Autodesk Fusion 360 part; units mm, degrees
(part 6 of 7)
sketch "Cut stock profile (62)" plane through (-287, 0, 0) normal (1, 0, 0) x (0, 0, -1) in component "rear left public turning fork"
  circle A0 centre (-38.1, 265) radius 5
ref_plane "WorkPlane1" through (-286, 0, 0) normal (1, 0, 0) x (0, 1, 0) in component "rear left public wheel axle"
sketch "New stock profile (103)" plane through (-286, 0, 0) normal (1, 0, 0) x (0, 0, -1) in component "rear left public wheel axle"
  circle A0 centre (-38.1, 265) radius 5
extrude "New 1''''''''''''''''''''''''''''''''''''''''''''''''''''''''''''''''''''''''''''''''''''''''''''''''''''''" add sketch "New stock profile (103)" along normal blind 42 separate body makes body 229 in component "rear left public wheel axle"
ref_plane "WorkPlane1" through (10, 0, 0) normal (1, 0, 0) x (0, 1, 0) in component "rear left public wheel"
sketch "New stock profile (104)" plane through (10, 0, 0) normal (1, 0, 0) x (0, 0, -1) in component "rear left public wheel"
  circle A0 centre (-10, 0) radius 38.1
  circle A1 centre (-10, 0) radius 5
extrude "New 1'''''''''''''''''''''''''''''''''''''''''''''''''''''''''''''''''''''''''''''''''''''''''''''''''''''''" add sketch "New stock profile (104)" against normal blind 26 separate body makes body 230 in component "rear left public wheel"
ref_plane "WorkPlane1" through (0, 0, 3.1) normal (0, 0, 1) x (1, 0, 0) in component "rear right public drive housing"
sketch "New stock profile (105)" plane through (0, 0, 3.1) normal (0, 0, 1) x (1, 0, 0) in component "rear right public drive housing"
  circle A0 centre (3, 3) radius 30
  circle A1 centre (3, 3) radius 20
extrude "New 1''''''''''''''''''''''''''''''''''''''''''''''''''''''''''''''''''''''''''''''''''''''''''''''''''''''''" add sketch "New stock profile (105)" along normal blind 48 separate body makes body 231 in component "rear right public drive housing"
ref_plane "WorkPlane2" through (0, 0, -1.9) normal (0, 0, 1) x (1, 0, 0) in component "rear right public drive housing"
sketch "Join stock profile (39)" plane through (0, 0, -1.9) normal (0, 0, 1) x (1, 0, 0) in component "rear right public drive housing"
  line L0 (15, 15) -> (29, 15)
  line L1 (29, 15) -> (29, 29)
  line L2 (29, 29) -> (15, 29)
  line L3 (15, 29) -> (15, 15)
extrude "Join 2''''''''''''''''''''''''''''''''''''''" add sketch "Join stock profile (39)" along normal blind 53 bodies 231 in component "rear right public drive housing"
ref_plane "WorkPlane3" through (0, 0, -4.4362) normal (0, 0, 1) x (1, 0, 0) in component "rear right public drive housing"
sketch "Join stock profile (1) (7)" plane through (0, 0, -4.4362) normal (0, 0, 1) x (1, 0, 0) in component "rear right public drive housing"
  line L0 (22, -33) -> (29, -33)
  line L1 (29, -33) -> (29, 28)
  line L2 (29, 28) -> (22, 28)
  line L3 (22, 28) -> (22, -33)
extrude "Join 3''''''" add sketch "Join stock profile (1) (7)" along normal blind 4.2863 bodies 231 in component "rear right public drive housing"
ref_plane "WorkPlane4" through (0, 0, -4.4362) normal (0, 0, 1) x (1, 0, 0) in component "rear right public drive housing"
sketch "Join stock profile (2) (8)" plane through (0, 0, -4.4362) normal (0, 0, 1) x (1, 0, 0) in component "rear right public drive housing"
  line L0 (25, -34) -> (90.7, -34)
  line L1 (90.7, -34) -> (90.7, -23)
  line L2 (90.7, -23) -> (25, -23)
  line L3 (25, -23) -> (25, -34)
extrude "Join 4''''''" add sketch "Join stock profile (2) (8)" along normal blind 4.2863 bodies 231 in component "rear right public drive housing"
ref_plane "WorkPlane5" through (0, 0, -4.4362) normal (0, 0, 1) x (1, 0, 0) in component "rear right public drive housing"
sketch "Join stock profile (3) (5)" plane through (0, 0, -4.4362) normal (0, 0, 1) x (1, 0, 0) in component "rear right public drive housing"
  line L0 (-33, 22) -> (28, 22)
  line L1 (28, 22) -> (28, 29)
  line L2 (28, 29) -> (-33, 29)
  line L3 (-33, 29) -> (-33, 22)
extrude "Join 5'''" add sketch "Join stock profile (3) (5)" along normal blind 4.2863 bodies 231 in component "rear right public drive housing"
ref_plane "WorkPlane6" through (0, 0, -4.4362) normal (0, 0, 1) x (1, 0, 0) in component "rear right public drive housing"
sketch "Join stock profile (4) (5)" plane through (0, 0, -4.4362) normal (0, 0, 1) x (1, 0, 0) in component "rear right public drive housing"
  line L0 (-34, 25) -> (-23, 25)
  line L1 (-23, 25) -> (-23, 90.7)
  line L2 (-23, 90.7) -> (-34, 90.7)
  line L3 (-34, 90.7) -> (-34, 25)
extrude "Join 6'''" add sketch "Join stock profile (4) (5)" along normal blind 4.2863 bodies 231 in component "rear right public drive housing"
ref_plane "WorkPlane7" through (0, 0, -4.4463) normal (0, 0, 1) x (1, 0, 0) in component "rear right public drive housing"
sketch "Cut stock profile (63)" plane through (0, 0, -4.4463) normal (0, 0, 1) x (1, 0, 0) in component "rear right public drive housing"
  circle A0 centre (60.15, -28.75) radius 2.5
extrude "Cut 7''''''''" cut sketch "Cut stock profile (63)" along normal blind 4.3063 bodies 231 in component "rear right public drive housing"
extrude "Extrude4''''''''''''''" [no effect] in component "rear right tab 1-1 socket screw"
ref_plane "WorkPlane8" through (0, 0, -4.4463) normal (0, 0, 1) x (1, 0, 0) in component "rear right public drive housing"
sketch "Cut stock profile (1) (17)" plane through (0, 0, -4.4463) normal (0, 0, 1) x (1, 0, 0) in component "rear right public drive housing"
  circle A0 centre (85.55, -28.75) radius 2.5
extrude "Cut 8'''" cut sketch "Cut stock profile (1) (17)" along normal blind 4.3063 bodies 231 in component "rear right public drive housing"
extrude "Extrude4'''''''''''''''" [no effect] in component "rear right tab 1-2 socket screw"
ref_plane "WorkPlane9" through (0, 0, -4.4463) normal (0, 0, 1) x (1, 0, 0) in component "rear right public drive housing"
sketch "Cut stock profile (2) (17)" plane through (0, 0, -4.4463) normal (0, 0, 1) x (1, 0, 0) in component "rear right public drive housing"
  circle A0 centre (-28.75, 60.15) radius 2.5
extrude "Cut 9'''" cut sketch "Cut stock profile (2) (17)" along normal blind 4.3063 bodies 231 in component "rear right public drive housing"
extrude "Extrude4''''''''''''''''" [no effect] in component "rear right tab 2-1 socket screw"
ref_plane "WorkPlane10" through (0, 0, -4.4463) normal (0, 0, 1) x (1, 0, 0) in component "rear right public drive housing"
sketch "Cut stock profile (3) (15)" plane through (0, 0, -4.4463) normal (0, 0, 1) x (1, 0, 0) in component "rear right public drive housing"
  circle A0 centre (-28.75, 85.55) radius 2.5
extrude "Cut 10'''" cut sketch "Cut stock profile (3) (15)" along normal blind 4.3063 bodies 231 in component "rear right public drive housing"
extrude "Extrude4'''''''''''''''''" [no effect] in component "rear right tab 2-2 socket screw"
ref_plane "WorkPlane11" through (0, 0, 50.65) normal (0, 0, 1) x (1, 0, 0) in component "rear right public drive housing"
sketch "Join stock profile (5) (5)" plane through (0, 0, 50.65) normal (0, 0, 1) x (1, 0, 0) in component "rear right public drive housing"
  line L0 (22, -33) -> (29, -33)
  line L1 (29, -33) -> (29, 28)
  line L2 (29, 28) -> (22, 28)
  line L3 (22, 28) -> (22, -33)
extrude "Join 11'''" add sketch "Join stock profile (5) (5)" along normal blind 3.6625 bodies 231 in component "rear right public drive housing"
ref_plane "WorkPlane12" through (0, 0, 50.65) normal (0, 0, 1) x (1, 0, 0) in component "rear right public drive housing"
sketch "Join stock profile (6) (5)" plane through (0, 0, 50.65) normal (0, 0, 1) x (1, 0, 0) in component "rear right public drive housing"
  line L0 (25, -34) -> (90.7, -34)
  line L1 (90.7, -34) -> (90.7, -23)
  line L2 (90.7, -23) -> (25, -23)
  line L3 (25, -23) -> (25, -34)
extrude "Join 12'''" add sketch "Join stock profile (6) (5)" along normal blind 3.6625 bodies 231 in component "rear right public drive housing"
ref_plane "WorkPlane13" through (0, 0, 50.65) normal (0, 0, 1) x (1, 0, 0) in component "rear right public drive housing"
sketch "Join stock profile (7) (5)" plane through (0, 0, 50.65) normal (0, 0, 1) x (1, 0, 0) in component "rear right public drive housing"
  line L0 (-33, 22) -> (28, 22)
  line L1 (28, 22) -> (28, 29)
  line L2 (28, 29) -> (-33, 29)
  line L3 (-33, 29) -> (-33, 22)
extrude "Join 13'''" add sketch "Join stock profile (7) (5)" along normal blind 3.6625 bodies 231 in component "rear right public drive housing"
ref_plane "WorkPlane14" through (0, 0, 50.65) normal (0, 0, 1) x (1, 0, 0) in component "rear right public drive housing"
sketch "Join stock profile (8) (5)" plane through (0, 0, 50.65) normal (0, 0, 1) x (1, 0, 0) in component "rear right public drive housing"
  line L0 (-34, 25) -> (-23, 25)
  line L1 (-23, 25) -> (-23, 90.7)
  line L2 (-23, 90.7) -> (-34, 90.7)
  line L3 (-34, 90.7) -> (-34, 25)
extrude "Join 14'''" add sketch "Join stock profile (8) (5)" along normal blind 3.6625 bodies 231 in component "rear right public drive housing"
ref_plane "WorkPlane15" through (0, 0, 50.64) normal (0, 0, 1) x (1, 0, 0) in component "rear right public drive housing"
sketch "Cut stock profile (4) (15)" plane through (0, 0, 50.64) normal (0, 0, 1) x (1, 0, 0) in component "rear right public drive housing"
  circle A0 centre (60.15, -28.75) radius 2.5
extrude "Cut 15'''" cut sketch "Cut stock profile (4) (15)" along normal blind 3.6825 bodies 231 in component "rear right public drive housing"
extrude "Extrude5''''''''''''''" [no effect] in component "rear right tab 1-1 socket screw"
extrude "Extrude2'''''''''''''''" [no effect] in component "rear right tab 1-1 locknut"
ref_plane "WorkPlane16" through (0, 0, 50.64) normal (0, 0, 1) x (1, 0, 0) in component "rear right public drive housing"
sketch "Cut stock profile (5) (13)" plane through (0, 0, 50.64) normal (0, 0, 1) x (1, 0, 0) in component "rear right public drive housing"
  circle A0 centre (85.55, -28.75) radius 2.5
extrude "Cut 16'''" cut sketch "Cut stock profile (5) (13)" along normal blind 3.6825 bodies 231 in component "rear right public drive housing"
extrude "Extrude5'''''''''''''''" [no effect] in component "rear right tab 1-2 socket screw"
extrude "Extrude2''''''''''''''''" [no effect] in component "rear right tab 1-2 locknut"
ref_plane "WorkPlane17" through (0, 0, 50.64) normal (0, 0, 1) x (1, 0, 0) in component "rear right public drive housing"
sketch "Cut stock profile (6) (5)" plane through (0, 0, 50.64) normal (0, 0, 1) x (1, 0, 0) in component "rear right public drive housing"
  circle A0 centre (-28.75, 60.15) radius 2.5
extrude "Cut 17'''" cut sketch "Cut stock profile (6) (5)" along normal blind 3.6825 bodies 231 in component "rear right public drive housing"
extrude "Extrude5''''''''''''''''" [no effect] in component "rear right tab 2-1 socket screw"
extrude "Extrude2'''''''''''''''''" [no effect] in component "rear right tab 2-1 locknut"
ref_plane "WorkPlane18" through (0, 0, 50.64) normal (0, 0, 1) x (1, 0, 0) in component "rear right public drive housing"
sketch "Cut stock profile (7) (5)" plane through (0, 0, 50.64) normal (0, 0, 1) x (1, 0, 0) in component "rear right public drive housing"
  circle A0 centre (-28.75, 85.55) radius 2.5
extrude "Cut 18'''" cut sketch "Cut stock profile (7) (5)" along normal blind 3.6825 bodies 231 in component "rear right public drive housing"
extrude "Extrude5'''''''''''''''''" [no effect] in component "rear right tab 2-2 socket screw"
extrude "Extrude2''''''''''''''''''" [no effect] in component "rear right tab 2-2 locknut"
ref_plane "WorkPlane1" through (0, 0, 6.1) normal (0, 0, 1) x (1, 0, 0) in component "rear right public motor reserve"
sketch "New stock profile (106)" plane through (0, 0, 6.1) normal (0, 0, 1) x (1, 0, 0) in component "rear right public motor reserve"
  circle A0 centre (19, 19) radius 19
extrude "New 1'''''''''''''''''''''''''''''''''''''''''''''''''''''''''''''''''''''''''''''''''''''''''''''''''''''''''" add sketch "New stock profile (106)" along normal blind 50.36 separate body makes body 232 in component "rear right public motor reserve"
ref_plane "WorkPlane1" through (0, 0, 68.1) normal (0, 0, 1) x (1, 0, 0) in component "rear right public turning fork"
sketch "New stock profile (107)" plane through (0, 0, 68.1) normal (0, 0, 1) x (1, 0, 0) in component "rear right public turning fork"
  circle A0 centre (-265, -265) radius 19.95
extrude "New 1''''''''''''''''''''''''''''''''''''''''''''''''''''''''''''''''''''''''''''''''''''''''''''''''''''''''''" add sketch "New stock profile (107)" along normal blind 23 separate body makes body 233 in component "rear right public turning fork"
ref_plane "WorkPlane2" through (0, 0, 68.1) normal (0, 0, 1) x (1, 0, 0) in component "rear right public turning fork"
sketch "Join stock profile (40)" plane through (0, 0, 68.1) normal (0, 0, 1) x (1, 0, 0) in component "rear right public turning fork"
  circle A0 centre (-265, -265) radius 25.5
extrude "Join 2'''''''''''''''''''''''''''''''''''''''" add sketch "Join stock profile (40)" along normal blind 5 bodies 233 in component "rear right public turning fork"
ref_plane "WorkPlane3" through (0, 0, 33.1) normal (0, 0, 1) x (1, 0, 0) in component "rear right public turning fork"
sketch "Join stock profile (1) (8)" plane through (0, 0, 33.1) normal (0, 0, 1) x (1, 0, 0) in component "rear right public turning fork"
  line L0 (-272, -286) -> (-258, -286)
  line L1 (-258, -286) -> (-258, -279)
  line L2 (-258, -279) -> (-272, -279)
  line L3 (-272, -279) -> (-272, -286)
extrude "Join 3'''''''" add sketch "Join stock profile (1) (8)" along normal blind 39 bodies 233 in component "rear right public turning fork"
ref_plane "WorkPlane4" through (0, 0, 33.1) normal (0, 0, 1) x (1, 0, 0) in component "rear right public turning fork"
sketch "Join stock profile (2) (9)" plane through (0, 0, 33.1) normal (0, 0, 1) x (1, 0, 0) in component "rear right public turning fork"
  line L0 (-272, -251) -> (-258, -251)
  line L1 (-258, -251) -> (-258, -244)
  line L2 (-258, -244) -> (-272, -244)
  line L3 (-272, -244) -> (-272, -251)
extrude "Join 4'''''''" add sketch "Join stock profile (2) (9)" along normal blind 39 bodies 233 in component "rear right public turning fork"
ref_plane "WorkPlane5" through (0, -287, 0) normal (0, 1, 0) x (0, 0, 1) in component "rear right public turning fork"
sketch "Cut stock profile (64)" plane through (0, -287, 0) normal (0, 1, 0) x (1, 0, 0) in component "rear right public turning fork"
  circle A0 centre (-265, -38.1) radius 5
ref_plane "WorkPlane1" through (0, -286, 0) normal (0, 1, 0) x (0, 0, 1) in component "rear right public wheel axle"
sketch "New stock profile (108)" plane through (0, -286, 0) normal (0, 1, 0) x (1, 0, 0) in component "rear right public wheel axle"
  circle A0 centre (-265, -38.1) radius 5
extrude "New 1'''''''''''''''''''''''''''''''''''''''''''''''''''''''''''''''''''''''''''''''''''''''''''''''''''''''''''" add sketch "New stock profile (108)" along normal blind 42 separate body makes body 234 in component "rear right public wheel axle"
ref_plane "WorkPlane1" through (0, 0, 3) normal (0, 0, 1) x (1, 0, 0) in component "rear right public wheel"
sketch "New stock profile (109)" plane through (0, 0, 3) normal (0, 0, 1) x (1, 0, 0) in component "rear right public wheel"
  circle A0 centre (-3, 0) radius 38.1
  circle A1 centre (-3, 0) radius 5
extrude "New 1''''''''''''''''''''''''''''''''''''''''''''''''''''''''''''''''''''''''''''''''''''''''''''''''''''''''''''" add sketch "New stock profile (109)" along normal blind 26 separate body makes body 235 in component "rear right public wheel"
ref_plane "WorkPlane1" through (0, 0, 38.1) normal (0, 0, 1) x (1, 0, 0)
sketch "Module joint datum" plane through (0, 0, 38.1) normal (0, 0, 1) x (1, 0, 0)
  point P0 (265, 265)
ref_plane "WorkPlane2" through (0, 0, 38.1) normal (0, 0, 1) x (1, 0, 0)
sketch "Module joint datum (1)" plane through (0, 0, 38.1) normal (0, 0, 1) x (1, 0, 0)
  point P0 (265, -265)
ref_plane "WorkPlane3" through (0, 0, 38.1) normal (0, 0, 1) x (1, 0, 0)
sketch "Module joint datum (2)" plane through (0, 0, 38.1) normal (0, 0, 1) x (1, 0, 0)
  point P0 (-265, 265)
ref_plane "WorkPlane4" through (0, 0, 38.1) normal (0, 0, 1) x (1, 0, 0)
sketch "Module joint datum (3)" plane through (0, 0, 38.1) normal (0, 0, 1) x (1, 0, 0)
  point P0 (-265, -265)
ref_plane "WorkPlane7" through (0, -22.225, 0) normal (0, 1, 0) x (0, 0, 1) in component "rear perimeter tube"
sketch "Cut stock profile (5) (14)" plane through (0, -22.225, 0) normal (0, 1, 0) x (1, 0, 0) in component "rear perimeter tube"
  line L0 (9.525, 1) -> (-9.525, 1)
  line L1 (-9.525, 1) -> (-9.525, -630.2)
  line L2 (-9.525, -630.2) -> (9.525, -630.2)
  line L3 (9.525, -630.2) -> (9.525, 1)
extrude "Cut 1" cut sketch "Cut stock profile (5) (14)" along normal blind 44.45 bodies 127 in component "rear perimeter tube"
ref_plane "WorkPlane8" through (-9.2, 0, 0) normal (1, 0, 0) x (0, 1, 0) in component "rear perimeter tube"
sketch "Cut stock profile (6) (6)" plane through (-9.2, 0, 0) normal (1, 0, 0) x (0, 0, -1) in component "rear perimeter tube"
  circle A0 centre (-509.75, -5.3) radius 6.55
extrude "Cut 1 (1)" cut sketch "Cut stock profile (6) (6)" against normal blind 4.5 bodies 127 in component "rear perimeter tube"
ref_plane "WorkPlane9" through (-9.2, 0, 0) normal (1, 0, 0) x (0, 1, 0) in component "rear perimeter tube"
sketch "Cut stock profile (7) (6)" plane through (-9.2, 0, 0) normal (1, 0, 0) x (0, 0, -1) in component "rear perimeter tube"
  circle A0 centre (-509.75, 15.7) radius 6.55
extrude "Cut 1 (2)" cut sketch "Cut stock profile (7) (6)" against normal blind 4.5 bodies 127 in component "rear perimeter tube"
ref_plane "WorkPlane10" through (-9.2, 0, 0) normal (1, 0, 0) x (0, 1, 0) in component "rear perimeter tube"
sketch "Cut stock profile (8) (2)" plane through (-9.2, 0, 0) normal (1, 0, 0) x (0, 0, -1) in component "rear perimeter tube"
  circle A0 centre (-119.45, -5.3) radius 6.55
extrude "Cut 1 (3)" cut sketch "Cut stock profile (8) (2)" against normal blind 4.5 bodies 127 in component "rear perimeter tube"
ref_plane "WorkPlane11" through (-9.2, 0, 0) normal (1, 0, 0) x (0, 1, 0) in component "rear perimeter tube"
sketch "Cut stock profile (9) (2)" plane through (-9.2, 0, 0) normal (1, 0, 0) x (0, 0, -1) in component "rear perimeter tube"
  circle A0 centre (-119.45, 15.7) radius 6.55
extrude "Cut 1 (4)" cut sketch "Cut stock profile (9) (2)" against normal blind 4.5 bodies 127 in component "rear perimeter tube"
ref_plane "WorkPlane7" through (9.2, 0, 0) normal (1, 0, 0) x (0, 1, 0) in component "right perimeter tube"
sketch "Cut stock profile (5) (15)" plane through (9.2, 0, 0) normal (1, 0, 0) x (0, 0, -1) in component "right perimeter tube"
  circle A0 centre (-535.15, -5.3) radius 6.55
extrude "Cut 1'" cut sketch "Cut stock profile (5) (15)" along normal blind 4.5 bodies 128 in component "right perimeter tube"
ref_plane "WorkPlane8" through (9.2, 0, 0) normal (1, 0, 0) x (0, 1, 0) in component "right perimeter tube"
sketch "Cut stock profile (6) (7)" plane through (9.2, 0, 0) normal (1, 0, 0) x (0, 0, -1) in component "right perimeter tube"
  circle A0 centre (-535.15, 15.7) radius 6.55
extrude "Cut 1 (1)'" cut sketch "Cut stock profile (6) (7)" along normal blind 4.5 bodies 128 in component "right perimeter tube"
ref_plane "WorkPlane9" through (9.2, 0, 0) normal (1, 0, 0) x (0, 1, 0) in component "right perimeter tube"
sketch "Cut stock profile (7) (7)" plane through (9.2, 0, 0) normal (1, 0, 0) x (0, 0, -1) in component "right perimeter tube"
  circle A0 centre (-144.85, -5.3) radius 6.55
extrude "Cut 1 (2)'" cut sketch "Cut stock profile (7) (7)" along normal blind 4.5 bodies 128 in component "right perimeter tube"
ref_plane "WorkPlane10" through (9.2, 0, 0) normal (1, 0, 0) x (0, 1, 0) in component "right perimeter tube"
sketch "Cut stock profile (8) (3)" plane through (9.2, 0, 0) normal (1, 0, 0) x (0, 0, -1) in component "right perimeter tube"
  circle A0 centre (-144.85, 15.7) radius 6.55
extrude "Cut 1 (3)'" cut sketch "Cut stock profile (8) (3)" along normal blind 4.5 bodies 128 in component "right perimeter tube"
ref_plane "WorkPlane5" through (9.2, 0, 0) normal (1, 0, 0) x (0, 1, 0) in component "right front return"
sketch "Cut stock profile (3) (16)" plane through (9.2, 0, 0) normal (1, 0, 0) x (0, 0, -1) in component "right front return"
  circle A0 centre (-119.45, -5.3) radius 6.55
extrude "Cut 1''" cut sketch "Cut stock profile (3) (16)" along normal blind 4.5 bodies 129 in component "right front return"
ref_plane "WorkPlane6" through (9.2, 0, 0) normal (1, 0, 0) x (0, 1, 0) in component "right front return"
sketch "Cut stock profile (4) (16)" plane through (9.2, 0, 0) normal (1, 0, 0) x (0, 0, -1) in component "right front return"
  circle A0 centre (-119.45, 15.7) radius 6.55
extrude "Cut 1 (1)''" cut sketch "Cut stock profile (4) (16)" along normal blind 4.5 bodies 129 in component "right front return"
ref_plane "WorkPlane3" through (0, -14.4752, 0) normal (0, 1, 0) x (0, 0, 1) in component "right floor sill"
sketch "Cut stock profile (1) (18)" plane through (0, -14.4752, 0) normal (0, 1, 0) x (1, 0, 0) in component "right floor sill"
  line L0 (4.0498, 1) -> (4.0498, -481)
  line L1 (4.0498, -481) -> (19.9502, -481)
  line L2 (19.9502, -481) -> (19.9502, 1)
  line L3 (19.9502, 1) -> (4.0498, 1)
extrude "Cut 1'''" cut sketch "Cut stock profile (1) (18)" along normal blind 15.9004 bodies 130 in component "right floor sill"
ref_plane "WorkPlane7" through (-9.2, 0, 0) normal (1, 0, 0) x (0, 1, 0) in component "left perimeter tube"
sketch "Cut stock profile (5) (16)" plane through (-9.2, 0, 0) normal (1, 0, 0) x (0, 0, -1) in component "left perimeter tube"
  circle A0 centre (-535.15, -5.3) radius 6.55
extrude "Cut 1''''" cut sketch "Cut stock profile (5) (16)" against normal blind 4.5 bodies 133 in component "left perimeter tube"
ref_plane "WorkPlane8" through (-9.2, 0, 0) normal (1, 0, 0) x (0, 1, 0) in component "left perimeter tube"
sketch "Cut stock profile (6) (8)" plane through (-9.2, 0, 0) normal (1, 0, 0) x (0, 0, -1) in component "left perimeter tube"
  circle A0 centre (-535.15, 15.7) radius 6.55
extrude "Cut 1 (1)'''" cut sketch "Cut stock profile (6) (8)" against normal blind 4.5 bodies 133 in component "left perimeter tube"
ref_plane "WorkPlane9" through (-9.2, 0, 0) normal (1, 0, 0) x (0, 1, 0) in component "left perimeter tube"
sketch "Cut stock profile (7) (8)" plane through (-9.2, 0, 0) normal (1, 0, 0) x (0, 0, -1) in component "left perimeter tube"
  circle A0 centre (-144.85, -5.3) radius 6.55
extrude "Cut 1 (2)''" cut sketch "Cut stock profile (7) (8)" against normal blind 4.5 bodies 133 in component "left perimeter tube"
ref_plane "WorkPlane10" through (-9.2, 0, 0) normal (1, 0, 0) x (0, 1, 0) in component "left perimeter tube"
sketch "Cut stock profile (8) (4)" plane through (-9.2, 0, 0) normal (1, 0, 0) x (0, 0, -1) in component "left perimeter tube"
  circle A0 centre (-144.85, 15.7) radius 6.55
extrude "Cut 1 (3)''" cut sketch "Cut stock profile (8) (4)" against normal blind 4.5 bodies 133 in component "left perimeter tube"
ref_plane "WorkPlane5" through (9.2, 0, 0) normal (1, 0, 0) x (0, 1, 0) in component "left front return"
sketch "Cut stock profile (3) (17)" plane through (9.2, 0, 0) normal (1, 0, 0) x (0, 0, -1) in component "left front return"
  circle A0 centre (-45.15, -5.3) radius 6.55
extrude "Cut 1'''''" cut sketch "Cut stock profile (3) (17)" along normal blind 4.5 bodies 134 in component "left front return"
ref_plane "WorkPlane6" through (9.2, 0, 0) normal (1, 0, 0) x (0, 1, 0) in component "left front return"
sketch "Cut stock profile (4) (17)" plane through (9.2, 0, 0) normal (1, 0, 0) x (0, 0, -1) in component "left front return"
  circle A0 centre (-45.15, 15.7) radius 6.55
extrude "Cut 1 (1)''''" cut sketch "Cut stock profile (4) (17)" along normal blind 4.5 bodies 134 in component "left front return"
ref_plane "WorkPlane3" through (0, -14.4752, 0) normal (0, 1, 0) x (0, 0, 1) in component "left floor sill"
sketch "Cut stock profile (1) (19)" plane through (0, -14.4752, 0) normal (0, 1, 0) x (1, 0, 0) in component "left floor sill"
  line L0 (-19.9502, 1) -> (-19.9502, -481)
  line L1 (-19.9502, -481) -> (-4.0498, -481)
  line L2 (-4.0498, -481) -> (-4.0498, 1)
  line L3 (-4.0498, 1) -> (-19.9502, 1)
extrude "Cut 1''''''" cut sketch "Cut stock profile (1) (19)" along normal blind 15.9004 bodies 135 in component "left floor sill"
ref_plane "WorkPlane6" through (0, 287, 0) normal (0, 1, 0) x (0, 0, 1) in component "front left public turning fork"
sketch "Cut stock profile (1) (20)" plane through (0, 287, 0) normal (0, 1, 0) x (1, 0, 0) in component "front left public turning fork"
  circle A0 centre (265, -38.1) radius 5
extrude "Cut 1'''''''" cut sketch "Cut stock profile (1) (20)" against normal blind 44 bodies 218 in component "front left public turning fork"
ref_plane "WorkPlane6" through (287, 0, 0) normal (1, 0, 0) x (0, 1, 0) in component "front right public turning fork"
sketch "Cut stock profile (1) (21)" plane through (287, 0, 0) normal (1, 0, 0) x (0, 0, -1) in component "front right public turning fork"
  circle A0 centre (-38.1, -265) radius 5
extrude "Cut 1''''''''" cut sketch "Cut stock profile (1) (21)" against normal blind 44 bodies 223 in component "front right public turning fork"
ref_plane "WorkPlane6" through (-287, 0, 0) normal (1, 0, 0) x (0, 1, 0) in component "rear left public turning fork"
sketch "Cut stock profile (1) (22)" plane through (-287, 0, 0) normal (1, 0, 0) x (0, 0, -1) in component "rear left public turning fork"
  circle A0 centre (-38.1, 265) radius 5
extrude "Cut 1'''''''''" cut sketch "Cut stock profile (1) (22)" along normal blind 44 bodies 228 in component "rear left public turning fork"
ref_plane "WorkPlane6" through (0, -287, 0) normal (0, 1, 0) x (0, 0, 1) in component "rear right public turning fork"
sketch "Cut stock profile (1) (23)" plane through (0, -287, 0) normal (0, 1, 0) x (1, 0, 0) in component "rear right public turning fork"
  circle A0 centre (-265, -38.1) radius 5
extrude "Cut 1''''''''''" cut sketch "Cut stock profile (1) (23)" along normal blind 44 bodies 233 in component "rear right public turning fork"
component "left perimeter tube" placed x (0, 1, 0) y (0, 0, 1) z (1, 0, 0) at (-340, 327.3, 89.4)
component "left front return" placed x (-1, 0, 0) y (0, 0, 1) z (0, 1, 0) at (327.3, 150, 89.4)
component "left blue side bumper" placed x (1, 0, 0) y (0, 1, 0) z (0, 0, 1) at (0, 378, 48)
component "left blue front bumper" placed x (1, 0, 0) y (0, 1, 0) z (0, 0, 1) at (378, 245, 48)
component "right perimeter tube" placed x (0, 1, 0) y (0, 0, 1) z (1, 0, 0) at (-340, -327.3, 89.4)
component "right front return" placed x (-1, 0, 0) y (0, 0, 1) z (0, 1, 0) at (327.3, -314.6, 89.4)
component "right blue side bumper" placed x (1, 0, 0) y (0, 1, 0) z (0, 0, 1) at (0, -378, 48)
component "right blue front bumper" placed x (1, 0, 0) y (0, 1, 0) z (0, 0, 1) at (378, -245, 48)
component "rear perimeter tube" placed x (-1, 0, 0) y (0, 0, 1) z (0, 1, 0) at (-327.3, -314.6, 89.4)
component "rear blue bumper" placed x (1, 0, 0) y (0, 1, 0) z (0, 0, 1) at (-378, 0, 48)
component "front left module tab spacer 1" placed x (1, 0, 0) y (0, 1, 0) z (0, 0, 1) at (198, 303.05, 78.32)
component "front left module tab spacer 2" placed x (1, 0, 0) y (0, 1, 0) z (0, 0, 1) at (303.05, 198, 78.32)
component "front right module tab spacer 1" placed x (1, 0, 0) y (0, 1, 0) z (0, 0, 1) at (303.05, -198, 78.32)
component "front right module tab spacer 2" placed x (1, 0, 0) y (0, 1, 0) z (0, 0, 1) at (198, -303.05, 78.32)
component "rear left module tab spacer 1" placed x (1, 0, 0) y (0, 1, 0) z (0, 0, 1) at (-303.05, 198, 78.32)
component "rear left module tab spacer 2" placed x (1, 0, 0) y (0, 1, 0) z (0, 0, 1) at (-198, 303.05, 78.32)
component "rear right module tab spacer 1" placed x (1, 0, 0) y (0, 1, 0) z (0, 0, 1) at (-198, -303.05, 78.32)
component "rear right module tab spacer 2" placed x (1, 0, 0) y (0, 1, 0) z (0, 0, 1) at (-303.05, -198, 78.32)
component "rear right hopper post" placed x (1, 0, 0) y (0, 1, 0) z (0, 0, 1) at (-188, -306, 115)
component "front right hopper post" placed x (1, 0, 0) y (0, 1, 0) z (0, 0, 1) at (176, -306, 115)
component "right floor sill" placed x (0, 1, 0) y (0, 0, 1) z (1, 0, 0) at (-330, -306, 227)
component "rear left hopper post" placed x (1, 0, 0) y (0, 1, 0) z (0, 0, 1) at (-188, 306, 115)
component "front left hopper post" placed x (1, 0, 0) y (0, 1, 0) z (0, 0, 1) at (176, 306, 115)
component "left floor sill" placed x (0, 1, 0) y (0, 0, 1) z (1, 0, 0) at (-330, 306, 227)
component "rear deck crossmember" placed x (-1, 0, 0) y (0, 0, 1) z (0, 1, 0) at (-188, -315, 113)
component "front deck crossmember" placed x (-1, 0, 0) y (0, 0, 1) z (0, 1, 0) at (176, -315, 113)
component "left electronics deck" placed x (1, 0, 0) y (0, 1, 0) z (0, 0, 1) at (-5.5, 149, 122)
component "right electronics deck" placed x (1, 0, 0) y (0, 1, 0) z (0, 0, 1) at (-5.5, -147.5, 122)
component "fore electronics deck bridge" placed x (1, 0, 0) y (0, 1, 0) z (0, 0, 1) at (110.5, 1.5, 122)
component "aft electronics deck bridge" placed x (1, 0, 0) y (0, 1, 0) z (0, 0, 1) at (-157.5, 1.5, 122)
component "battery cradle floor" placed x (1, 0, 0) y (0, 1, 0) z (0, 0, 1) at (-41.5, 1.5, 44)
component "battery cradle wall -44" placed x (1, 0, 0) y (0, 1, 0) z (0, 0, 1) at (-41.5, -42, 48)
component "battery cradle wall 43" placed x (1, 0, 0) y (0, 1, 0) z (0, 0, 1) at (-41.5, 45, 48)
component "battery secured envelope" placed x (1, 0, 0) y (0, 1, 0) z (0, 0, 1) at (-41.5, 2, 48)
component "distribution enclosure reserve" placed x (1, 0, 0) y (0, 1, 0) z (0, 0, 1) at (105, -3, 129)
component "robot controller reserve" placed x (1, 0, 0) y (0, 1, 0) z (0, 0, 1) at (-79.5, 108, 129)
component "field radio reserve" placed x (1, 0, 0) y (0, 1, 0) z (0, 0, 1) at (-88.5, -118.5, 129)
component "drive controller reserve 1" placed x (1, 0, 0) y (0, 1, 0) z (0, 0, 1) at (-120.5, -204, 129)
component "drive controller reserve 2" placed x (1, 0, 0) y (0, 1, 0) z (0, 0, 1) at (-120.5, 204, 129)
component "drive controller reserve 3" placed x (1, 0, 0) y (0, 1, 0) z (0, 0, 1) at (-42.5, -204, 129)
component "drive controller reserve 4" placed x (1, 0, 0) y (0, 1, 0) z (0, 0, 1) at (-42.5, 204, 129)
component "drive controller reserve 5" placed x (1, 0, 0) y (0, 1, 0) z (0, 0, 1) at (35.5, -204, 129)
component "drive controller reserve 6" placed x (1, 0, 0) y (0, 1, 0) z (0, 0, 1) at (35.5, 204, 129)
component "drive controller reserve 7" placed x (1, 0, 0) y (0, 1, 0) z (0, 0, 1) at (113.5, -204, 129)
component "drive controller reserve 8" placed x (1, 0, 0) y (0, 1, 0) z (0, 0, 1) at (113.5, 204, 129)
component "hopper back panel" placed x (1, 0, 0) y (0, 1, 0) z (0, 0, 1) at (-332, 0, 232)
component "right hopper wall" placed x (1, 0, 0) y (0, 1, 0) z (0, 0, 1) at (-91, -313, 232)
component "right hopper front wing" placed x (1, 0, 0) y (0, 1, 0) z (0, 0, 1) at (150, -199, 232)
component "right cross feed deck" placed x (1, 0, 0) y (0, 1, 0) z (0, 0, 1) at (-91, -199, 230)
component "right front elevator upright" placed x (1, 0, 0) y (0, 1, 0) z (0, 0, 1) at (183, -105, 111)
component "right rear elevator upright" placed x (1, 0, 0) y (0, 1, 0) z (0, 0, 1) at (319, -105, 113)
component "right elevator upper tie" placed x (0, 1, 0) y (0, 0, 1) z (1, 0, 0) at (181, -105, 637)
component "right inside lift belt" placed x (1, 0, 0) y (0, 1, 0) z (0, 0, 1) at (196, -91, 86)
component "right outside lift belt" placed x (1, 0, 0) y (0, 1, 0) z (0, 0, 1) at (301, -91, 86)
component "right lift shelf 1" placed x (1, 0, 0) y (0, 1, 0) z (0, 0, 1) at (244, -81, 99)
component "right lift shelf 2" placed x (1, 0, 0) y (0, 1, 0) z (0, 0, 1) at (244, -81, 258)
component "right lift shelf 3" placed x (1, 0, 0) y (0, 1, 0) z (0, 0, 1) at (244, -81, 417)
component "right lift shelf 4" placed x (1, 0, 0) y (0, 1, 0) z (0, 0, 1) at (244, -81, 576)
component "right intake ramp" placed x (0, 1, 0) y (0.257178, 0, 0.966364) z (0.966364, 0, -0.257178) at (213, -60, 48)
component "left hopper wall" placed x (1, 0, 0) y (0, 1, 0) z (0, 0, 1) at (-91, 313, 232)
component "left hopper front wing" placed x (1, 0, 0) y (0, 1, 0) z (0, 0, 1) at (150, 199, 232)
component "left cross feed deck" placed x (1, 0, 0) y (0, 1, 0) z (0, 0, 1) at (-91, 199, 230)
component "left front elevator upright" placed x (1, 0, 0) y (0, 1, 0) z (0, 0, 1) at (183, 105, 111)
component "left rear elevator upright" placed x (1, 0, 0) y (0, 1, 0) z (0, 0, 1) at (319, 105, 113)
component "left elevator upper tie" placed x (0, 1, 0) y (0, 0, 1) z (1, 0, 0) at (181, 105, 637)
component "left inside lift belt" placed x (1, 0, 0) y (0, 1, 0) z (0, 0, 1) at (196, 91, 86)
component "left outside lift belt" placed x (1, 0, 0) y (0, 1, 0) z (0, 0, 1) at (301, 91, 86)
component "left lift shelf 1" placed x (1, 0, 0) y (0, 1, 0) z (0, 0, 1) at (244, 81, 99)
component "left lift shelf 2" placed x (1, 0, 0) y (0, 1, 0) z (0, 0, 1) at (244, 81, 258)
component "left lift shelf 3" placed x (1, 0, 0) y (0, 1, 0) z (0, 0, 1) at (244, 81, 417)
component "left lift shelf 4" placed x (1, 0, 0) y (0, 1, 0) z (0, 0, 1) at (244, 81, 576)
component "left intake ramp" placed x (0, 1, 0) y (0.257178, 0, 0.966364) z (0.966364, 0, -0.257178) at (213, 60, 48)
component "central fore-aft feed deck" placed x (1, 0, 0) y (0, 1, 0) z (0, 0, 1) at (-90.5, 0, 230)
component "left lower lift stub shaft" placed x (-1, 0, 0) y (0, 0, 1) z (0, 1, 0) at (248, 88, 84)
component "right lower lift stub shaft" placed x (-1, 0, 0) y (0, 0, 1) z (0, 1, 0) at (248, -116, 84)
component "left upper lift stub shaft" placed x (-1, 0, 0) y (0, 0, 1) z (0, 1, 0) at (248, 88, 622)
component "right upper lift stub shaft" placed x (-1, 0, 0) y (0, 0, 1) z (0, 1, 0) at (248, -116, 622)
component "ground intake roller" placed x (-1, 0, 0) y (0, 0, 1) z (0, 1, 0) at (285.7664, -126, 342.4358)
component "right intake bearing arm" placed x (0.994522, 0, -0.104528) y (0, 1, 0) z (0.104528, 0, 0.994522) at (275, -150, 240)
component "right intake pivot plate" placed x (0, -1, 0) y (-0.17238, 0, 0.98503) z (-0.98503, 0, -0.17238) at (315, -150, 247)
component "right intake pivot axle" placed x (-1, 0, 0) y (0, 0, 1) z (0, 1, 0) at (275, -150, 240)
component "right intake journal" placed x (-1, 0, 0) y (0, 0, 1) z (0, 1, 0) at (285.7664, -150, 342.4358)
component "right upper head cheek" placed x (1, 0, 0) y (0, 1, 0) z (0, 0, 1) at (236, -150, 562)
component "left intake bearing arm" placed x (0.994522, 0, -0.104528) y (0, 1, 0) z (0.104528, 0, 0.994522) at (275, 150, 240)
component "left intake pivot plate" placed x (0, -1, 0) y (-0.17238, 0, 0.98503) z (-0.98503, 0, -0.17238) at (315, 150, 247)
component "left intake pivot axle" placed x (-1, 0, 0) y (0, 0, 1) z (0, 1, 0) at (275, 100, 240)
component "left intake journal" placed x (-1, 0, 0) y (0, 0, 1) z (0, 1, 0) at (285.7664, 126, 342.4358)
component "left upper head cheek" placed x (1, 0, 0) y (0, 1, 0) z (0, 0, 1) at (236, 150, 562)
component "right scoring wheel" placed x (0, -1, 0) y (0.5, 0, 0.866025) z (-0.866025, 0, 0.5) at (259.6506, -104, 588.5)
component "right scoring spindle" placed x (0, -1, 0) y (0.5, 0, 0.866025) z (-0.866025, 0, 0.5) at (269.1769, -104, 583)
component "right upper guide" placed x (0, 1, 0) y (-0.841019, 0, 0.541006) z (0.541006, 0, 0.841019) at (190, -80, 548)
component "right scoring bearing bridge -33" placed x (-1, 0, 0) y (0, 0, 1) z (0, 1, 0) at (266.5788, -146, 584.5)
component "right scoring bearing bridge 33" placed x (-1, 0, 0) y (0, 0, 1) z (0, 1, 0) at (209.4212, -146, 617.5)
component "left scoring wheel" placed x (0, -1, 0) y (0.5, 0, 0.866025) z (-0.866025, 0, 0.5) at (259.6506, 104, 588.5)
component "left scoring spindle" placed x (0, -1, 0) y (0.5, 0, 0.866025) z (-0.866025, 0, 0.5) at (269.1769, 104, 583)
component "left upper guide" placed x (0, 1, 0) y (-0.841019, 0, 0.541006) z (0.541006, 0, 0.841019) at (190, 80, 548)
component "left scoring bearing bridge -33" placed x (-1, 0, 0) y (0, 0, 1) z (0, 1, 0) at (266.5788, 104, 584.5)
component "left scoring bearing bridge 33" placed x (-1, 0, 0) y (0, 0, 1) z (0, 1, 0) at (209.4212, 104, 617.5)
component "left feed diverter pivot" placed x (-1, 0, 0) y (0, 0, 1) z (0, 1, 0) at (156, 76, 548)
component "right feed diverter pivot" placed x (-1, 0, 0) y (0, 0, 1) z (0, 1, 0) at (156, -100, 548)
component "feed diverter vane" placed x (1, 0, 0) y (0, 1, 0) z (0, 0, 1) at (156, 0, 548)
component "front left public wheel" placed x (-1, 0, 0) y (0, 0, 1) z (0, 1, 0) at (268, 255, 38.1)
component "front left public drive housing" placed x (1, 0, 0) y (0, 1, 0) z (0, 0, 1) at (268, 268, 70)
component "front left public motor reserve" placed x (1, 0, 0) y (0, 1, 0) z (0, 0, 1) at (268, 268, 115)
component "front right public wheel" placed x (-1, 0, 0) y (0, 0, 1) z (0, 1, 0) at (268, -281, 38.1)
component "front right public drive housing" placed x (1, 0, 0) y (0, 1, 0) z (0, 0, 1) at (268, -268, 70)
component "front right public motor reserve" placed x (1, 0, 0) y (0, 1, 0) z (0, 0, 1) at (268, -268, 115)
component "rear left public wheel" placed x (-1, 0, 0) y (0, 0, 1) z (0, 1, 0) at (-268, 255, 38.1)
component "rear left public drive housing" placed x (1, 0, 0) y (0, 1, 0) z (0, 0, 1) at (-268, 268, 70)
component "rear left public motor reserve" placed x (1, 0, 0) y (0, 1, 0) z (0, 0, 1) at (-268, 268, 115)
component "rear right public wheel" placed x (-1, 0, 0) y (0, 0, 1) z (0, 1, 0) at (-268, -281, 38.1)
component "rear right public drive housing" placed x (1, 0, 0) y (0, 1, 0) z (0, 0, 1) at (-268, -268, 70)
component "rear right public motor reserve" placed x (1, 0, 0) y (0, 1, 0) z (0, 0, 1) at (-268, -268, 115)
component "right public scoring motor envelope" placed x (0, -1, 0) y (0.5, 0, 0.866025) z (-0.866025, 0, 0.5) at (213.7513, -104, 615)
component "left public scoring motor envelope" placed x (0, -1, 0) y (0.5, 0, 0.866025) z (-0.866025, 0, 0.5) at (213.7513, 104, 615)
component "rear lift custody gate" placed x (1, 0, 0) y (0, 1, 0) z (0, 0, 1) at (169, 0, 134)
component "front lift custody guide" placed x (1, 0, 0) y (0, 1, 0) z (0, 0, 1) at (329, 0, 221)
component "left mast" placed x (1, 0, 0) y (0, 1, 0) z (0, 0, 1) at (-180, 326, 114.8)
component "left aft mast" placed x (1, 0, 0) y (0, 1, 0) z (0, 0, 1) at (-280, 326, 114.8)
component "left upper bearing plate" placed x (1, 0, 0) y (0, 1, 0) z (0, 0, 1) at (-230, 317, 744)
component "left lower bearing plate" placed x (1, 0, 0) y (0, 1, 0) z (0, 0, 1) at (-240, 313.5, 551)
component "left lead screw envelope" placed x (1, 0, 0) y (0, 1, 0) z (0, 0, 1) at (-240, 305, 557)
component "left lift motor envelope" placed x (1, 0, 0) y (0, 1, 0) z (0, 0, 1) at (-240, 258, 577)
component "left reduction envelope" placed x (1, 0, 0) y (0, 1, 0) z (0, 0, 1) at (-240, 280, 557)
component "left driven nut" placed x (1, 0, 0) y (0, 1, 0) z (0, 0, 1) at (-240, 305.5, 711)
component "left nut link" placed x (1, 0, 0) y (0, 1, 0) z (0, 0, 1) at (-240, 306, 701)
component "left crosshead cheek" placed x (1, 0, 0) y (0, 1, 0) z (0, 0, 1) at (-204.5, 303.5, 687)
component "left forward carriage sleeve" placed x (1, 0, 0) y (0, 1, 0) z (0, 0, 1) at (-180, 326, 682)
component "left aft carriage sleeve" placed x (1, 0, 0) y (0, 1, 0) z (0, 0, 1) at (-280, 326, 682)
component "left extension sleeve" placed x (0, 1, 0) y (0, 0, 1) z (1, 0, 0) at (-173, 72, 739)
component "left sleeve pedestal" placed x (1, 0, 0) y (0, 1, 0) z (0, 0, 1) at (-153, 72, 701)
component "left extending rail" placed x (0, 1, 0) y (0, 0, 1) z (1, 0, 0) at (-220, 72, 739)
component "left crown hook" placed x (1, 0, 0) y (0, 0, 1) z (0, -1, 0) at (0, 94, 0)
component "right mast" placed x (1, 0, 0) y (0, 1, 0) z (0, 0, 1) at (-180, -326, 114.8)
component "right aft mast" placed x (1, 0, 0) y (0, 1, 0) z (0, 0, 1) at (-280, -326, 114.8)
component "right upper bearing plate" placed x (1, 0, 0) y (0, 1, 0) z (0, 0, 1) at (-230, -317, 744)
component "right lower bearing plate" placed x (1, 0, 0) y (0, 1, 0) z (0, 0, 1) at (-240, -313.5, 551)
component "right lead screw envelope" placed x (1, 0, 0) y (0, 1, 0) z (0, 0, 1) at (-240, -305, 557)
component "right lift motor envelope" placed x (1, 0, 0) y (0, 1, 0) z (0, 0, 1) at (-240, -258, 577)
component "right reduction envelope" placed x (1, 0, 0) y (0, 1, 0) z (0, 0, 1) at (-240, -280, 557)
component "right driven nut" placed x (1, 0, 0) y (0, 1, 0) z (0, 0, 1) at (-240, -305.5, 711)
component "right nut link" placed x (1, 0, 0) y (0, 1, 0) z (0, 0, 1) at (-240, -306, 701)
component "right crosshead cheek" placed x (1, 0, 0) y (0, 1, 0) z (0, 0, 1) at (-204.5, -303.5, 687)
component "right forward carriage sleeve" placed x (1, 0, 0) y (0, 1, 0) z (0, 0, 1) at (-180, -326, 682)
component "right aft carriage sleeve" placed x (1, 0, 0) y (0, 1, 0) z (0, 0, 1) at (-280, -326, 682)
component "right extension sleeve" placed x (0, 1, 0) y (0, 0, 1) z (1, 0, 0) at (-173, -72, 739)
component "right sleeve pedestal" placed x (1, 0, 0) y (0, 1, 0) z (0, 0, 1) at (-153, -72, 701)
component "right extending rail" placed x (0, 1, 0) y (0, 0, 1) z (1, 0, 0) at (-220, -72, 739)
component "right crown hook" placed x (1, 0, 0) y (0, 0, 1) z (0, -1, 0) at (0, -82, 0)
component "crosshead lift bridge" placed x (-1, 0, 0) y (0, 0, 1) z (0, 1, 0) at (-151, -315, 691)
component "rail synchronizing tie" placed x (1, 0, 0) y (0, 1, 0) z (0, 0, 1) at (163, 0, 750)
component "extension bearing beam" placed x (1, 0, 0) y (0, 1, 0) z (0, 0, 1) at (32, 0, 701)
component "extension rear bearing and stop" placed x (0, 1, 0) y (0, 0, 1) z (1, 0, 0) at (-74, 0, 733)
component "extension forward bearing" placed x (0, 1, 0) y (0, 0, 1) z (1, 0, 0) at (193, 0, 733)
component "extension screw envelope" placed x (0, 1, 0) y (0, 0, 1) z (1, 0, 0) at (-74, 0, 733)
component "extension deployment nut" placed x (0, 1, 0) y (0, 0, 1) z (1, 0, 0) at (153, 0, 733)
component "extension nut hanger" placed x (1, 0, 0) y (0, 1, 0) z (0, 0, 1) at (163, 0, 746)
component "extension motor envelope" placed x (0, 1, 0) y (0, 0, 1) z (1, 0, 0) at (205, 0, 733)
component "extension motor foot" placed x (1, 0, 0) y (0, 1, 0) z (0, 0, 1) at (215, 0, 716)
component "rear right crossmember backing plate" placed x (1, 0, 0) y (0, 1, 0) z (0, 0, 1) at (0, 0, 0)
component "rear left crossmember backing plate" placed x (1, 0, 0) y (0, 1, 0) z (0, 0, 1) at (0, 0, 0)
component "front right crossmember backing plate" placed x (1, 0, 0) y (0, 1, 0) z (0, 0, 1) at (0, 0, 0)
component "front left crossmember backing plate" placed x (1, 0, 0) y (0, 1, 0) z (0, 0, 1) at (0, 0, 0)
component "front left rail mount 1-1 weld boss" placed x (1, 0, 0) y (0, 1, 0) z (0, 0, 1) at (0, 0, 0)
component "front left rail mount 1-1 M6 cap screw" placed x (1, 0, 0) y (0, 1, 0) z (0, 0, 1) at (0, 0, 0)
component "front left rail mount 1-2 weld boss" placed x (1, 0, 0) y (0, 1, 0) z (0, 0, 1) at (0, 0, 0)
component "front left rail mount 1-2 M6 cap screw" placed x (1, 0, 0) y (0, 1, 0) z (0, 0, 1) at (0, 0, 0)
component "front left tab 1-1 socket screw" placed x (1, 0, 0) y (0, 1, 0) z (0, 0, 1) at (0, 0, 0)
component "front left tab 1-1 locknut" placed x (1, 0, 0) y (0, 1, 0) z (0, 0, 1) at (0, 0, 0)
component "front left tab 1-2 socket screw" placed x (1, 0, 0) y (0, 1, 0) z (0, 0, 1) at (0, 0, 0)
component "front left tab 1-2 locknut" placed x (1, 0, 0) y (0, 1, 0) z (0, 0, 1) at (0, 0, 0)
component "front left rail mount 2-1 weld boss" placed x (1, 0, 0) y (0, 1, 0) z (0, 0, 1) at (0, 0, 0)
component "front left rail mount 2-1 M6 cap screw" placed x (1, 0, 0) y (0, 1, 0) z (0, 0, 1) at (0, 0, 0)
component "front left rail mount 2-2 weld boss" placed x (1, 0, 0) y (0, 1, 0) z (0, 0, 1) at (0, 0, 0)
component "front left rail mount 2-2 M6 cap screw" placed x (1, 0, 0) y (0, 1, 0) z (0, 0, 1) at (0, 0, 0)
component "front left tab 2-1 socket screw" placed x (1, 0, 0) y (0, 1, 0) z (0, 0, 1) at (0, 0, 0)
component "front left tab 2-1 locknut" placed x (1, 0, 0) y (0, 1, 0) z (0, 0, 1) at (0, 0, 0)
component "front left tab 2-2 socket screw" placed x (1, 0, 0) y (0, 1, 0) z (0, 0, 1) at (0, 0, 0)
component "front left tab 2-2 locknut" placed x (1, 0, 0) y (0, 1, 0) z (0, 0, 1) at (0, 0, 0)
component "front right rail mount 1-1 weld boss" placed x (1, 0, 0) y (0, 1, 0) z (0, 0, 1) at (0, 0, 0)
component "front right rail mount 1-1 M6 cap screw" placed x (1, 0, 0) y (0, 1, 0) z (0, 0, 1) at (0, 0, 0)
component "front right rail mount 1-2 weld boss" placed x (1, 0, 0) y (0, 1, 0) z (0, 0, 1) at (0, 0, 0)
component "front right rail mount 1-2 M6 cap screw" placed x (1, 0, 0) y (0, 1, 0) z (0, 0, 1) at (0, 0, 0)
component "front right tab 1-1 socket screw" placed x (1, 0, 0) y (0, 1, 0) z (0, 0, 1) at (0, 0, 0)
component "front right tab 1-1 locknut" placed x (1, 0, 0) y (0, 1, 0) z (0, 0, 1) at (0, 0, 0)
component "front right tab 1-2 socket screw" placed x (1, 0, 0) y (0, 1, 0) z (0, 0, 1) at (0, 0, 0)
component "front right tab 1-2 locknut" placed x (1, 0, 0) y (0, 1, 0) z (0, 0, 1) at (0, 0, 0)
component "front right rail mount 2-1 weld boss" placed x (1, 0, 0) y (0, 1, 0) z (0, 0, 1) at (0, 0, 0)
component "front right rail mount 2-1 M6 cap screw" placed x (1, 0, 0) y (0, 1, 0) z (0, 0, 1) at (0, 0, 0)
component "front right rail mount 2-2 weld boss" placed x (1, 0, 0) y (0, 1, 0) z (0, 0, 1) at (0, 0, 0)
component "front right rail mount 2-2 M6 cap screw" placed x (1, 0, 0) y (0, 1, 0) z (0, 0, 1) at (0, 0, 0)
component "front right tab 2-1 socket screw" placed x (1, 0, 0) y (0, 1, 0) z (0, 0, 1) at (0, 0, 0)
component "front right tab 2-1 locknut" placed x (1, 0, 0) y (0, 1, 0) z (0, 0, 1) at (0, 0, 0)
component "front right tab 2-2 socket screw" placed x (1, 0, 0) y (0, 1, 0) z (0, 0, 1) at (0, 0, 0)
component "front right tab 2-2 locknut" placed x (1, 0, 0) y (0, 1, 0) z (0, 0, 1) at (0, 0, 0)
component "rear left rail mount 1-1 weld boss" placed x (1, 0, 0) y (0, 1, 0) z (0, 0, 1) at (0, 0, 0)
component "rear left rail mount 1-1 M6 cap screw" placed x (1, 0, 0) y (0, 1, 0) z (0, 0, 1) at (0, 0, 0)
component "rear left rail mount 1-2 weld boss" placed x (1, 0, 0) y (0, 1, 0) z (0, 0, 1) at (0, 0, 0)
component "rear left rail mount 1-2 M6 cap screw" placed x (1, 0, 0) y (0, 1, 0) z (0, 0, 1) at (0, 0, 0)
component "rear left tab 1-1 socket screw" placed x (1, 0, 0) y (0, 1, 0) z (0, 0, 1) at (0, 0, 0)
component "rear left tab 1-1 locknut" placed x (1, 0, 0) y (0, 1, 0) z (0, 0, 1) at (0, 0, 0)
component "rear left tab 1-2 socket screw" placed x (1, 0, 0) y (0, 1, 0) z (0, 0, 1) at (0, 0, 0)
component "rear left tab 1-2 locknut" placed x (1, 0, 0) y (0, 1, 0) z (0, 0, 1) at (0, 0, 0)
component "rear left rail mount 2-1 weld boss" placed x (1, 0, 0) y (0, 1, 0) z (0, 0, 1) at (0, 0, 0)
component "rear left rail mount 2-1 M6 cap screw" placed x (1, 0, 0) y (0, 1, 0) z (0, 0, 1) at (0, 0, 0)
component "rear left rail mount 2-2 weld boss" placed x (1, 0, 0) y (0, 1, 0) z (0, 0, 1) at (0, 0, 0)
component "rear left rail mount 2-2 M6 cap screw" placed x (1, 0, 0) y (0, 1, 0) z (0, 0, 1) at (0, 0, 0)
component "rear left tab 2-1 socket screw" placed x (1, 0, 0) y (0, 1, 0) z (0, 0, 1) at (0, 0, 0)
component "rear left tab 2-1 locknut" placed x (1, 0, 0) y (0, 1, 0) z (0, 0, 1) at (0, 0, 0)
component "rear left tab 2-2 socket screw" placed x (1, 0, 0) y (0, 1, 0) z (0, 0, 1) at (0, 0, 0)
component "rear left tab 2-2 locknut" placed x (1, 0, 0) y (0, 1, 0) z (0, 0, 1) at (0, 0, 0)
component "rear right rail mount 1-1 weld boss" placed x (1, 0, 0) y (0, 1, 0) z (0, 0, 1) at (0, 0, 0)
component "rear right rail mount 1-1 M6 cap screw" placed x (1, 0, 0) y (0, 1, 0) z (0, 0, 1) at (0, 0, 0)
component "rear right rail mount 1-2 weld boss" placed x (1, 0, 0) y (0, 1, 0) z (0, 0, 1) at (0, 0, 0)
component "rear right rail mount 1-2 M6 cap screw" placed x (1, 0, 0) y (0, 1, 0) z (0, 0, 1) at (0, 0, 0)
component "rear right tab 1-1 socket screw" placed x (1, 0, 0) y (0, 1, 0) z (0, 0, 1) at (0, 0, 0)
component "rear right tab 1-1 locknut" placed x (1, 0, 0) y (0, 1, 0) z (0, 0, 1) at (0, 0, 0)
component "rear right tab 1-2 socket screw" placed x (1, 0, 0) y (0, 1, 0) z (0, 0, 1) at (0, 0, 0)
component "rear right tab 1-2 locknut" placed x (1, 0, 0) y (0, 1, 0) z (0, 0, 1) at (0, 0, 0)
component "rear right rail mount 2-1 weld boss" placed x (1, 0, 0) y (0, 1, 0) z (0, 0, 1) at (0, 0, 0)
component "rear right rail mount 2-1 M6 cap screw" placed x (1, 0, 0) y (0, 1, 0) z (0, 0, 1) at (0, 0, 0)
component "rear right rail mount 2-2 weld boss" placed x (1, 0, 0) y (0, 1, 0) z (0, 0, 1) at (0, 0, 0)
component "rear right rail mount 2-2 M6 cap screw" placed x (1, 0, 0) y (0, 1, 0) z (0, 0, 1) at (0, 0, 0)
component "rear right tab 2-1 socket screw" placed x (1, 0, 0) y (0, 1, 0) z (0, 0, 1) at (0, 0, 0)
component "rear right tab 2-1 locknut" placed x (1, 0, 0) y (0, 1, 0) z (0, 0, 1) at (0, 0, 0)
component "rear right tab 2-2 socket screw" placed x (1, 0, 0) y (0, 1, 0) z (0, 0, 1) at (0, 0, 0)
component "rear right tab 2-2 locknut" placed x (1, 0, 0) y (0, 1, 0) z (0, 0, 1) at (0, 0, 0)
component "front left public turning fork" placed x (1, 0, 0) y (0, 1, 0) z (0, 0, 1) at (0, 0, 0)
component "front left public wheel axle" placed x (1, 0, 0) y (0, 1, 0) z (0, 0, 1) at (0, 0, 0)
component "front right public turning fork" placed x (1, 0, 0) y (0, 1, 0) z (0, 0, 1) at (0, 0, 0)
component "front right public wheel axle" placed x (1, 0, 0) y (0, 1, 0) z (0, 0, 1) at (0, 0, 0)